CBP-0000-RevE-CAD-checkpoint003 (Autodesk Fusion 360 design; units mm, degrees)
part number: 2026-09-21-21-13-08-575
part number: 2026-09-22-14-43-03-767
part number: 2026-09-22-14-43-32-423
part number: 2026-09-22-14-58-32-491
part number: 2026-09-22-14-58-32-570
part number: 2026-09-22-14-58-32-641
part number: 2026-09-22-14-58-32-649
part number: 2026-09-22-14-58-32-656
part number: 2026-09-22-14-58-32-663
part number: 2026-09-22-14-58-32-671
part number: 2026-09-22-14-58-32-679
part number: 2026-09-22-14-58-32-687
part number: 2026-09-22-14-58-32-694
part number: 2026-09-22-14-58-32-777
part number: 2026-09-22-14-58-32-866
part number: 2026-09-22-15-02-12-520
part number: 2026-09-22-15-02-12-611
part number: 2026-09-22-15-02-12-705
part number: 2026-09-22-15-02-12-797
part number: 2026-09-22-15-02-12-894
part number: 2026-09-22-15-04-06-454
Autodesk Fusion 360 part; units mm, degrees
sketch "SK-1100-01_BASE_OUTLINE_PARAMETRIC" plane through (0, 0, 0) normal (0, 1, 0) x (1, 0, 0) in component "CBP-1100_BASE_PLATE"
  line L0 (150, 130) -> (-150, 130)
  line L1 (-150, 130) -> (-150, -130)
  line L2 (-150, -130) -> (150, -130)
  line L3 (150, -130) -> (150, 130)
  line L4 (150, 130) -> (-150, -130) construction
  line L5 (-150, 130) -> (150, -130) construction
  dimension "d4" = 300
  dimension "d5" = 260
  constraint horizontal L0
  constraint perpendicular L0 L1
  constraint parallel L0 L2
  constraint parallel L1 L3
  constraint coincident L4 origin
  constraint coincident L5 origin
  measures "d4" distance of L0.start L0.end
  measures "d5" distance of L0 L2
extrude "EX-1100-01_BASE_STOCK" add sketch "SK-1100-01_BASE_OUTLINE_PARAMETRIC" along normal blind 12 makes body 1 in component "CBP-1100_BASE_PLATE"
sketch "SK-1100-02_CLEARANCE_APERTURE" plane through (0, 0, 0) normal (0, 1, 0) x (1, 0, 0) in component "CBP-1100_BASE_PLATE"
  line L0 (74, 49) -> (-74, 49)
  line L1 (-74, 49) -> (-74, -49)
  line L2 (-74, -49) -> (74, -49)
  line L3 (74, -49) -> (74, 49)
  dimension "d56" = 148
  dimension "d57" = 98
  dimension "d58" = 74
  dimension "d59" = 49
  constraint horizontal L0
  constraint vertical L1
  constraint horizontal L2
  constraint vertical L3
  measures "d56" horizontal distance of L0.start L0.end
  measures "d57" vertical distance of L0.end L1.end
  measures "d58" horizontal distance of origin L0.start
  measures "d59" vertical distance of origin L0.start
extrude "CUT-1100-01_BED_SWEEP_APERTURE" cut sketch "SK-1100-02_CLEARANCE_APERTURE" along normal blind 12 bodies 1 in component "CBP-1100_BASE_PLATE"
sketch "SK-1100-03_FOUR_BASE_MOUNTS" plane through (0, 0, 0) normal (0, 1, 0) x (1, 0, 0) in component "CBP-1100_BASE_PLATE"
  circle A0 centre (-130, -110) radius 4.5
  circle A1 centre (-130, 110) radius 4.5
  circle A2 centre (130, -110) radius 4.5
  circle A3 centre (130, 110) radius 4.5
  dimension "d62" = 130
  dimension "d63" = 110
  dimension "d64" = 9
  dimension "d65" = 110
  dimension "d66" = 130
  constraint vertical A0.centre A1.centre
  constraint equal A0 A1
  constraint horizontal A0.centre A2.centre
  constraint equal A0 A2
  constraint vertical A2.centre A3.centre
  constraint horizontal A1.centre A3.centre
  constraint equal A0 A3
  measures "d62" horizontal distance of origin A0.centre
  measures "d63" vertical distance of origin A0.centre
  measures "d64" diameter of A0
  measures "d65" vertical distance of origin A1.centre
  measures "d66" horizontal distance of origin A2.centre
extrude "CUT-1100-02_FOUR_M8_MOUNTS" cut sketch "SK-1100-03_FOUR_BASE_MOUNTS" along normal blind 12 bodies 1 in component "CBP-1100_BASE_PLATE"
sketch "SK-1200-01_COLUMN_SECTION" plane through (0, 0, 0) normal (0, 1, 0) x (1, 0, 0) in component "CBP-1200_40MM_Z_COLUMN"
  line L0 (20, 20) -> (-20, 20)
  line L1 (-20, 20) -> (-20, -20)
  line L2 (-20, -20) -> (20, -20)
  line L3 (20, -20) -> (20, 20)
  dimension "d69" = 40
  dimension "d70" = 40
  dimension "d71" = 20
  dimension "d72" = 20
  constraint horizontal L0
  constraint vertical L1
  constraint horizontal L2
  constraint vertical L3
  measures "d69" horizontal distance of L0.start L0.end
  measures "d70" vertical distance of L0.end L1.end
  measures "d71" horizontal distance of origin L0.start
  measures "d72" vertical distance of origin L0.start
extrude "EX-CBP-1200_COLUMN_ENVELOPE" add sketch "SK-1200-01_COLUMN_SECTION" along normal blind 180 separate body makes body 2 in component "CBP-1200_40MM_Z_COLUMN"
sketch "SK-1210-01_BEAM_SECTION" plane through (0, 0, 0) normal (0, 1, 0) x (1, 0, 0) in component "CBP-1210_Z_CROSSBEAM_ENVELOPE"
  line L0 (110, 20) -> (-110, 20)
  line L1 (-110, 20) -> (-110, -20)
  line L2 (-110, -20) -> (110, -20)
  line L3 (110, -20) -> (110, 20)
  dimension "d75" = 220
  dimension "d76" = 40
  dimension "d77" = 110
  dimension "d78" = 20
  constraint horizontal L0
  constraint vertical L1
  constraint horizontal L2
  constraint vertical L3
  measures "d75" horizontal distance of L0.start L0.end
  measures "d76" vertical distance of L0.end L1.end
  measures "d77" horizontal distance of origin L0.start
  measures "d78" vertical distance of origin L0.start
extrude "EX-CBP-1210_CROSSBEAM_ENVELOPE" add sketch "SK-1210-01_BEAM_SECTION" along normal blind 40 separate body makes body 3 in component "CBP-1210_Z_CROSSBEAM_ENVELOPE"
sketch "SK-2100-01_STAGE_OUTLINE" plane through (0, 0, 0) normal (0, 1, 0) x (1, 0, 0) in component "CBP-2100_CARBON_XY_STAGE"
  line L0 (56, 42) -> (-56, 42)
  line L1 (-56, 42) -> (-56, -42)
  line L2 (-56, -42) -> (56, -42)
  line L3 (56, -42) -> (56, 42)
  dimension "d81" = 112
  dimension "d82" = 84
  dimension "d83" = 56
  dimension "d84" = 42
  constraint horizontal L0
  constraint vertical L1
  constraint horizontal L2
  constraint vertical L3
  measures "d81" horizontal distance of L0.start L0.end
  measures "d82" vertical distance of L0.end L1.end
  measures "d83" horizontal distance of origin L0.start
  measures "d84" vertical distance of origin L0.start
extrude "EX-CBP-2100_2MM_STAGE_STOCK" add sketch "SK-2100-01_STAGE_OUTLINE" along normal blind 2 separate body makes body 4 in component "CBP-2100_CARBON_XY_STAGE"
sketch "SK-3100-01_BED_OUTLINE" plane through (0, 0, 0) normal (0, 1, 0) x (1, 0, 0) in component "CBP-3100_BED_SUBSTRATE"
  line L0 (38, 25) -> (-38, 25)
  line L1 (-38, 25) -> (-38, -25)
  line L2 (-38, -25) -> (38, -25)
  line L3 (38, -25) -> (38, 25)
  dimension "d87" = 76
  dimension "d88" = 50
  dimension "d89" = 38
  dimension "d90" = 25
  constraint horizontal L0
  constraint vertical L1
  constraint horizontal L2
  constraint vertical L3
  measures "d87" horizontal distance of L0.start L0.end
  measures "d88" vertical distance of L0.end L1.end
  measures "d89" horizontal distance of origin L0.start
  measures "d90" vertical distance of origin L0.start
extrude "EX-CBP-3100_BED_SUBSTRATE_STOCK" add sketch "SK-3100-01_BED_OUTLINE" along normal blind 3 separate body makes body 5 in component "CBP-3100_BED_SUBSTRATE"
sketch "SK-3110-01_SURFACE_OUTLINE" plane through (0, 0, 0) normal (0, 1, 0) x (1, 0, 0) in component "CBP-3110_BUILD_SURFACE"
  line L0 (38, 25) -> (-38, 25)
  line L1 (-38, 25) -> (-38, -25)
  line L2 (-38, -25) -> (38, -25)
  line L3 (38, -25) -> (38, 25)
  dimension "d93" = 76
  dimension "d94" = 50
  dimension "d95" = 38
  dimension "d96" = 25
  constraint horizontal L0
  constraint vertical L1
  constraint horizontal L2
  constraint vertical L3
  measures "d93" horizontal distance of L0.start L0.end
  measures "d94" vertical distance of L0.end L1.end
  measures "d95" horizontal distance of origin L0.start
  measures "d96" vertical distance of origin L0.start
extrude "EX-CBP-3110_BUILD_SURFACE_FILM" add sketch "SK-3110-01_SURFACE_OUTLINE" along normal blind 0.25 separate body makes body 6 in component "CBP-3110_BUILD_SURFACE"
sketch "SK-P201-01_X_RAIL_ENVELOPE" plane through (0, 0, 0) normal (0, 1, 0) x (1, 0, 0) in component "CBP-P201_MGN7_X_RAIL_130_PROXY"
  line L0 (65, 3.5) -> (-65, 3.5)
  line L1 (-65, 3.5) -> (-65, -3.5)
  line L2 (-65, -3.5) -> (65, -3.5)
  line L3 (65, -3.5) -> (65, 3.5)
  dimension "d110" = 130
  dimension "d111" = 7
  dimension "d112" = 65
  dimension "d113" = 3.5
  constraint horizontal L0
  constraint vertical L1
  constraint horizontal L2
  constraint vertical L3
  measures "d110" horizontal distance of L0.start L0.end
  measures "d111" vertical distance of L0.end L1.end
  measures "d112" horizontal distance of origin L0.start
  measures "d113" vertical distance of origin L0.start
extrude "EX-CBP-P201_X_RAIL_ENVELOPE" add sketch "SK-P201-01_X_RAIL_ENVELOPE" along normal blind 4.8 separate body makes body 7 in component "CBP-P201_MGN7_X_RAIL_130_PROXY"
sketch "SK-P202-01_X_BLOCK_CAP" plane through (0, 0, 0) normal (0, 1, 0) x (1, 0, 0) in component "CBP-P202_MGN7H_X_BLOCK_PROXY"
  line L0 (15.4, 8.5) -> (-15.4, 8.5)
  line L1 (-15.4, 8.5) -> (-15.4, -8.5)
  line L2 (-15.4, -8.5) -> (15.4, -8.5)
  line L3 (15.4, -8.5) -> (15.4, 8.5)
  dimension "d116" = 30.8
  dimension "d117" = 17
  dimension "d118" = 15.4
  dimension "d119" = 8.5
  constraint horizontal L0
  constraint vertical L1
  constraint horizontal L2
  constraint vertical L3
  measures "d116" horizontal distance of L0.start L0.end
  measures "d117" vertical distance of L0.end L1.end
  measures "d118" horizontal distance of origin L0.start
  measures "d119" vertical distance of origin L0.start
extrude "EX-CBP-P202_X_BLOCK_UPPER_ENVELOPE" add sketch "SK-P202-01_X_BLOCK_CAP" along normal blind 3.2 separate body makes body 8 in component "CBP-P202_MGN7H_X_BLOCK_PROXY"
sketch "SK-2200-01_BRIDGE_ENVELOPE" plane through (0, 0, 0) normal (0, 1, 0) x (1, 0, 0) in component "CBP-2200_CARBON_X_BRIDGE"
  line L0 (5, 70) -> (-5, 70)
  line L1 (-5, 70) -> (-5, -70)
  line L2 (-5, -70) -> (5, -70)
  line L3 (5, -70) -> (5, 70)
  dimension "d122" = 10
  dimension "d123" = 140
  dimension "d124" = 5
  dimension "d125" = 70
  constraint horizontal L0
  constraint vertical L1
  constraint horizontal L2
  constraint vertical L3
  measures "d122" horizontal distance of L0.start L0.end
  measures "d123" vertical distance of L0.end L1.end
  measures "d124" horizontal distance of origin L0.start
  measures "d125" vertical distance of origin L0.start
extrude "EX-CBP-2200_BRIDGE_STOCK" add sketch "SK-2200-01_BRIDGE_ENVELOPE" along normal blind 10 separate body makes body 9 in component "CBP-2200_CARBON_X_BRIDGE"
sketch "SK-P203-01_Y_RAIL_ENVELOPE" plane through (0, 0, 0) normal (0, 1, 0) x (1, 0, 0) in component "CBP-P203_MGN7_Y_RAIL_110_PROXY"
  line L0 (3.5, 55) -> (-3.5, 55)
  line L1 (-3.5, 55) -> (-3.5, -55)
  line L2 (-3.5, -55) -> (3.5, -55)
  line L3 (3.5, -55) -> (3.5, 55)
  dimension "d128" = 7
  dimension "d129" = 110
  dimension "d130" = 3.5
  dimension "d131" = 55
  constraint horizontal L0
  constraint vertical L1
  constraint horizontal L2
  constraint vertical L3
  measures "d128" horizontal distance of L0.start L0.end
  measures "d129" vertical distance of L0.end L1.end
  measures "d130" horizontal distance of origin L0.start
  measures "d131" vertical distance of origin L0.start
extrude "EX-CBP-P203_Y_RAIL_ENVELOPE" add sketch "SK-P203-01_Y_RAIL_ENVELOPE" along normal blind 4.8 separate body makes body 10 in component "CBP-P203_MGN7_Y_RAIL_110_PROXY"
sketch "SK-P204-01_Y_BLOCK_CAP" plane through (0, 0, 0) normal (0, 1, 0) x (1, 0, 0) in component "CBP-P204_MGN7H_Y_BLOCK_PROXY"
  line L0 (8.5, 15.4) -> (-8.5, 15.4)
  line L1 (-8.5, 15.4) -> (-8.5, -15.4)
  line L2 (-8.5, -15.4) -> (8.5, -15.4)
  line L3 (8.5, -15.4) -> (8.5, 15.4)
  dimension "d134" = 17
  dimension "d135" = 30.8
  dimension "d136" = 8.5
  dimension "d137" = 15.4
  constraint horizontal L0
  constraint vertical L1
  constraint horizontal L2
  constraint vertical L3
  measures "d134" horizontal distance of L0.start L0.end
  measures "d135" vertical distance of L0.end L1.end
  measures "d136" horizontal distance of origin L0.start
  measures "d137" vertical distance of origin L0.start
extrude "EX-CBP-P204_Y_BLOCK_UPPER_ENVELOPE" add sketch "SK-P204-01_Y_BLOCK_CAP" along normal blind 3.2 separate body makes body 11 in component "CBP-P204_MGN7H_Y_BLOCK_PROXY"
sketch "SK-1300-01_SHIM_OUTLINE" plane through (0, 0, 0) normal (0, 1, 0) x (1, 0, 0) in component "CBP-1300_X_RAIL_ALIGNMENT_SHIM"
  line L0 (65, 6) -> (-65, 6)
  line L1 (-65, 6) -> (-65, -6)
  line L2 (-65, -6) -> (65, -6)
  line L3 (65, -6) -> (65, 6)
  dimension "d142" = 130
  dimension "d143" = 12
  dimension "d144" = 65
  dimension "d145" = 6
  constraint horizontal L0
  constraint vertical L1
  constraint horizontal L2
  constraint vertical L3
  measures "d142" horizontal distance of L0.start L0.end
  measures "d143" vertical distance of L0.end L1.end
  measures "d144" horizontal distance of origin L0.start
  measures "d145" vertical distance of origin L0.start
extrude "EX-CBP-1300_SHIM_STOCK" add sketch "SK-1300-01_SHIM_OUTLINE" along normal blind 2 separate body makes body 12 in component "CBP-1300_X_RAIL_ALIGNMENT_SHIM"
component "10_FRAME" placed x (1, 0, 0) y (0, 1, 0) z (0, 0, 1) at (0, 0, 0)
component "20_XY_MOTION" placed x (1, 0, 0) y (0, 1, 0) z (0, 0, 1) at (0, 0, 0)
component "30_BED" placed x (1, 0, 0) y (0, 1, 0) z (0, 0, 1) at (0, 0, 0)
component "40_Z_AXIS" placed x (1, 0, 0) y (0, 1, 0) z (0, 0, 1) at (0, 0, 0)
component "50_TOOLHEAD" placed x (1, 0, 0) y (0, 1, 0) z (0, 0, 1) at (0, 0, 0)
component "60_CPAP_COOLING" placed x (1, 0, 0) y (0, 1, 0) z (0, 0, 1) at (0, 0, 0)
component "70_ELECTRONICS" placed x (1, 0, 0) y (0, 1, 0) z (0, 0, 1) at (0, 0, 0)
component "80_HARNESS" placed x (1, 0, 0) y (0, 1, 0) z (0, 0, 1) at (0, 0, 0)
component "CBP-1100_BASE_PLATE" placed x (1, 0, 0) y (0, 1, 0) z (0, 0, 1) at (0, 0, 0) in component "10_FRAME"
component "CBP-1200_40MM_Z_COLUMN" placed x (1, 0, 0) y (0, 1, 0) z (0, 0, 1) at (-160, 12, -150) in component "10_FRAME"
component "CBP-1200_40MM_Z_COLUMN" placed x (1, 0, 0) y (0, 1, 0) z (0, 0, 1) at (160, 12, -150) in component "10_FRAME"
component "CBP-1210_Z_CROSSBEAM_ENVELOPE" placed x (1, 0, 0) y (0, 1, 0) z (0, 0, 1) at (0, 252, -150) in component "10_FRAME"
component "CBP-1300_X_RAIL_ALIGNMENT_SHIM" placed x (1, 0, 0) y (0, 1, 0) z (0, 0, 1) at (0, 12, -60) in component "10_FRAME"
component "CBP-1300_X_RAIL_ALIGNMENT_SHIM" placed x (1, 0, 0) y (0, 1, 0) z (0, 0, 1) at (0, 12, 60) in component "10_FRAME"
component "CBP-2100_CARBON_XY_STAGE" placed x (1, 0, 0) y (0, 1, 0) z (0, 0, 1) at (0, 80, 0) in component "20_XY_MOTION"
component "CBP-P201_MGN7_X_RAIL_130_PROXY" placed x (1, 0, 0) y (0, 1, 0) z (0, 0, 1) at (0, 54, -60) in component "20_XY_MOTION"
component "CBP-P201_MGN7_X_RAIL_130_PROXY" placed x (1, 0, 0) y (0, 1, 0) z (0, 0, 1) at (0, 54, 60) in component "20_XY_MOTION"
component "CBP-P202_MGN7H_X_BLOCK_PROXY" placed x (1, 0, 0) y (0, 1, 0) z (0, 0, 1) at (0, 58.8, -60) in component "20_XY_MOTION"
component "CBP-P202_MGN7H_X_BLOCK_PROXY" placed x (1, 0, 0) y (0, 1, 0) z (0, 0, 1) at (0, 58.8, 60) in component "20_XY_MOTION"
component "CBP-2200_CARBON_X_BRIDGE" placed x (1, 0, 0) y (0, 1, 0) z (0, 0, 1) at (0, 62, 0) in component "20_XY_MOTION"
component "CBP-P203_MGN7_Y_RAIL_110_PROXY" placed x (1, 0, 0) y (0, 1, 0) z (0, 0, 1) at (0, 72, 0) in component "20_XY_MOTION"
component "CBP-P204_MGN7H_Y_BLOCK_PROXY" placed x (1, 0, 0) y (0, 1, 0) z (0, 0, 1) at (0, 76.8, 0) in component "20_XY_MOTION"
component "CBP-3100_BED_SUBSTRATE" placed x (1, 0, 0) y (0, 1, 0) z (0, 0, 1) at (0, 82, 0) in component "30_BED"
component "CBP-3110_BUILD_SURFACE" placed x (1, 0, 0) y (0, 1, 0) z (0, 0, 1) at (0, 85, 0) in component "30_BED"
equation "base_x = 300 mm"
equation "base_y = 260 mm"
equation "base_t = 12 mm"
equation "d4 = base_x"
equation "d5 = base_y"
equation "d6 = base_t"
equation "base_bolt_inset = 20 mm" comment "Edge to mounting hole center"
equation "base_mount_d = 9 mm" comment "M8 clearance through holes"
equation "base_corner_r = 8 mm" comment "Outside vertical corner radius"
equation "travel_x = 64 mm" comment "Nominal useful X travel"
equation "travel_y = 40 mm" comment "Nominal useful Y travel"
equation "travel_z = 60 mm" comment "Useful nozzle Z range"
equation "bed_x = 76 mm" comment "Build surface X"
equation "bed_y = 50 mm" comment "Build surface Y"
equation "bed_t = 3 mm" comment "Development bed carrier thickness"
equation "bed_surface_t = 0.25 mm" comment "Build surface film allowance"
equation "stage_x = 112 mm" comment "Planar carrier outer X envelope; provisional"
equation "stage_y = 84 mm" comment "Planar carrier outer Y envelope; provisional"
equation "stage_t = 2 mm" comment "Carrier material thickness; provisional"
equation "guide_x = 320 mm" comment "Planar guide envelope X"
equation "guide_y = 260 mm" comment "Planar guide envelope Y"
equation "guide_t = 6 mm" comment "Guide plate stock allowance"
equation "guide_gap = 0.08 mm" comment "Prototype capture clearance; must verify fabrication"
equation "aperture_x = bed_x + travel_x + 8 mm" comment "Minimum bed and boat swept aperture X"
equation "aperture_y = bed_y + travel_y + 8 mm" comment "Minimum bed and boat swept aperture Y"
equation "tower_span = 220 mm" comment "Z tower outside support span"
equation "tower_y = 90 mm" comment "Tower axis Y from machine origin"
equation "tower_h = 180 mm" comment "Tower support height above base"
equation "tower_section = 40 mm" comment "Structural column nominal section"
equation "motor_flange = 56.4 mm" comment "Nanotec SCB5618L4204-B reference envelope only"
equation "motor_body_l = 76.5 mm" comment "Motor reference body length"
equation "motor_shaft_d = 8 mm" comment "Motor reference shaft diameter"
equation "drum_r = 25 mm" comment "Drive drum pitch radius; adjustable development parameter"
equation "belt_w = 9 mm" comment "Owned belt width; pitch and interfaces unconfirmed"
equation "anchor_x = 150 mm" comment "Drive anchor reference X offset"
equation "anchor_y = 150 mm" comment "Drive anchor reference Y offset"
equation "hose_od = 22 mm" comment "Provisional hose outside diameter; owned hose to be identified"
equation "hotend_z_envelope = 180 mm" comment "Stationary XY extrusion envelope allowance"
equation "toolhead_xy_envelope = 140 mm" comment "Multi-input extrusion service envelope"
equation "nozzle_d = 0.5 mm" comment "Maximum nozzle under retained race rules"
equation "fastener_m3_clear = 3.4 mm" comment "Ordinary M3 clearance"
equation "fastener_m5_clear = 5.5 mm" comment "Ordinary M5 clearance"
equation "fastener_m6_clear = 6.6 mm" comment "Ordinary M6 clearance"
equation "d56 = aperture_x"
equation "d57 = aperture_y"
equation "d58 = aperture_x / 2"
equation "d59 = aperture_y / 2"
equation "d60 = base_t"
equation "d62 = base_x / 2 - base_bolt_inset"
equation "d63 = base_y / 2 - base_bolt_inset"
equation "d64 = base_mount_d"
equation "d65 = base_y / 2 - base_bolt_inset"
equation "d66 = base_x / 2 - base_bolt_inset"
equation "d67 = base_t"
equation "d69 = tower_section"
equation "d70 = tower_section"
equation "d71 = tower_section / 2"
equation "d72 = tower_section / 2"
equation "d73 = tower_h"
equation "d75 = tower_span"
equation "d76 = tower_section"
equation "d77 = tower_span / 2"
equation "d78 = tower_section / 2"
equation "d79 = tower_section"
equation "d81 = stage_x"
equation "d82 = stage_y"
equation "d83 = stage_x / 2"
equation "d84 = stage_y / 2"
equation "d85 = stage_t"
equation "d87 = bed_x"
equation "d88 = bed_y"
equation "d89 = bed_x / 2"
equation "d90 = bed_y / 2"
equation "d91 = bed_t"
equation "d93 = bed_x"
equation "d94 = bed_y"
equation "d95 = bed_x / 2"
equation "d96 = bed_y / 2"
equation "d97 = bed_surface_t"
equation "x_rail_l = 130 mm" comment "X rail cut length; MGN7 candidate"
equation "y_rail_l = 110 mm" comment "Y rail cut length; MGN7 candidate"
equation "x_rail_sep = 120 mm" comment "Center-to-center X rail spacing"
equation "mgn7_rail_w = 7 mm" comment "HIWIN MGN7 rail envelope width"
equation "mgn7_rail_h = 4.8 mm" comment "HIWIN MGN7 rail envelope height"
equation "mgn7h_block_l = 30.8 mm" comment "HIWIN MGN7H block overall length"
equation "mgn7h_block_w = 17 mm" comment "HIWIN MGN7H block overall width"
equation "mgn7h_block_cap_h = 3.2 mm" comment "8 mm overall assembly height less 4.8 mm rail height; proxy cap only"
equation "bridge_w = 10 mm" comment "X moving bridge X-section"
equation "bridge_span = 140 mm" comment "X moving bridge length along machine Y"
equation "bridge_h = 10 mm" comment "X moving bridge vertical envelope"
equation "d110 = x_rail_l"
equation "d111 = mgn7_rail_w"
equation "d112 = x_rail_l / 2"
equation "d113 = mgn7_rail_w / 2"
equation "d114 = mgn7_rail_h"
equation "d116 = mgn7h_block_l"
equation "d117 = mgn7h_block_w"
equation "d118 = mgn7h_block_l / 2"
equation "d119 = mgn7h_block_w / 2"
equation "d120 = mgn7h_block_cap_h"
equation "d122 = bridge_w"
equation "d123 = bridge_span"
equation "d124 = bridge_w / 2"
equation "d125 = bridge_span / 2"
equation "d126 = bridge_h"
equation "d128 = mgn7_rail_w"
equation "d129 = y_rail_l"
equation "d130 = mgn7_rail_w / 2"
equation "d131 = y_rail_l / 2"
equation "d132 = mgn7_rail_h"
equation "d134 = mgn7h_block_w"
equation "d135 = mgn7h_block_l"
equation "d136 = mgn7h_block_w / 2"
equation "d137 = mgn7h_block_l / 2"
equation "d138 = mgn7h_block_cap_h"
equation "x_shim_w = 12 mm" comment "Machined X-rail support strip width across machine Y"
equation "x_shim_t = 2 mm" comment "Matched X-rail shim thickness; reference until measured"
equation "d142 = x_rail_l"
equation "d143 = x_shim_w"
equation "d144 = x_rail_l / 2"
equation "d145 = x_shim_w / 2"
equation "d146 = x_shim_t"
equation "tower_center_span = 180 mm" comment "Center-to-center distance of two rear Z columns"
named bodies: "CBP-1100_BASE_STOCK", "CBP-1200_COLUMN_ENVELOPE", "CBP-1210_CROSSBEAM_ENVELOPE", "CBP-2100_2MM_STAGE_STOCK", "CBP-3100_BED_SUBSTRATE_STOCK", "CBP-3110_BUILD_SURFACE_FILM", "CBP-P201_X_RAIL_ENVELOPE", "CBP-P202_X_BLOCK_UPPER_ENVELOPE", "CBP-2200_BRIDGE_STOCK", "CBP-P203_Y_RAIL_ENVELOPE", "CBP-P204_Y_BLOCK_UPPER_ENVELOPE", "CBP-1300_SHIM_STOCK"
